Autodesk Fusion 360 part; units mm, degrees
(part 2 of 2)
component "05_magnet_11_N 弧形磁钢 内侧N极" placed x (1, 0, 0) y (0, 1, 0) z (0, 0, 1) at (0, 0, 0) in component "A 旋转总成 | ROTOR"
component "05_magnet_12_S 弧形磁钢 内侧S极" placed x (1, 0, 0) y (0, 1, 0) z (0, 0, 1) at (0, 0, 0) in component "A 旋转总成 | ROTOR"
component "05_magnet_13_N 弧形磁钢 内侧N极" placed x (1, 0, 0) y (0, 1, 0) z (0, 0, 1) at (0, 0, 0) in component "A 旋转总成 | ROTOR"
component "05_magnet_14_S 弧形磁钢 内侧S极" placed x (1, 0, 0) y (0, 1, 0) z (0, 0, 1) at (0, 0, 0) in component "A 旋转总成 | ROTOR"
component "10_inner_spacer 内圈隔垫" placed x (1, 0, 0) y (0, 1, 0) z (0, 0, 1) at (0, 0, 0) in component "A 旋转总成 | ROTOR"
component "13_sensor_magnet 两极径向测角磁铁" placed x (1, 0, 0) y (0, 1, 0) z (0, 0, 1) at (0, 0, 0) in component "A 旋转总成 | ROTOR"
component "06_stator_carrier 铝固定座" placed x (1, 0, 0) y (0, 1, 0) z (0, 0, 1) at (0, 0, 0) in component "B 固定总成 | STATOR + SENSOR"
component "07_stator_stack 12 槽叠片铁芯 H4" placed x (1, 0, 0) y (0, 1, 0) z (0, 0, 1) at (0, 0, 0) in component "B 固定总成 | STATOR + SENSOR"
component "08_coil_01_Ap Ap 32匝绕组包络" placed x (1, 0, 0) y (0, 1, 0) z (0, 0, 1) at (0, 0, 0) in component "B 固定总成 | STATOR + SENSOR"
component "08_coil_02_An An 32匝绕组包络" placed x (1, 0, 0) y (0, 1, 0) z (0, 0, 1) at (0, 0, 0) in component "B 固定总成 | STATOR + SENSOR"
component "08_coil_03_Bn Bn 32匝绕组包络" placed x (1, 0, 0) y (0, 1, 0) z (0, 0, 1) at (0, 0, 0) in component "B 固定总成 | STATOR + SENSOR"
component "08_coil_04_Bp Bp 32匝绕组包络" placed x (1, 0, 0) y (0, 1, 0) z (0, 0, 1) at (0, 0, 0) in component "B 固定总成 | STATOR + SENSOR"
component "08_coil_05_Cp Cp 32匝绕组包络" placed x (1, 0, 0) y (0, 1, 0) z (0, 0, 1) at (0, 0, 0) in component "B 固定总成 | STATOR + SENSOR"
component "08_coil_06_Cn Cn 32匝绕组包络" placed x (1, 0, 0) y (0, 1, 0) z (0, 0, 1) at (0, 0, 0) in component "B 固定总成 | STATOR + SENSOR"
component "08_coil_07_An An 32匝绕组包络" placed x (1, 0, 0) y (0, 1, 0) z (0, 0, 1) at (0, 0, 0) in component "B 固定总成 | STATOR + SENSOR"
component "08_coil_08_Ap Ap 32匝绕组包络" placed x (1, 0, 0) y (0, 1, 0) z (0, 0, 1) at (0, 0, 0) in component "B 固定总成 | STATOR + SENSOR"
component "08_coil_09_Bp Bp 32匝绕组包络" placed x (1, 0, 0) y (0, 1, 0) z (0, 0, 1) at (0, 0, 0) in component "B 固定总成 | STATOR + SENSOR"
component "08_coil_10_Bn Bn 32匝绕组包络" placed x (1, 0, 0) y (0, 1, 0) z (0, 0, 1) at (0, 0, 0) in component "B 固定总成 | STATOR + SENSOR"
component "08_coil_11_Cn Cn 32匝绕组包络" placed x (1, 0, 0) y (0, 1, 0) z (0, 0, 1) at (0, 0, 0) in component "B 固定总成 | STATOR + SENSOR"
component "08_coil_12_Cp Cp 32匝绕组包络" placed x (1, 0, 0) y (0, 1, 0) z (0, 0, 1) at (0, 0, 0) in component "B 固定总成 | STATOR + SENSOR"
component "09_bearing_1 MR52ZZ 轴承包络" placed x (1, 0, 0) y (0, 1, 0) z (0, 0, 1) at (0, 0, 0) in component "B 固定总成 | STATOR + SENSOR"
component "09_bearing_2 MR52ZZ 轴承包络" placed x (1, 0, 0) y (0, 1, 0) z (0, 0, 1) at (0, 0, 0) in component "B 固定总成 | STATOR + SENSOR"
component "11_lower_outer_retainer 轴承外圈挡环" placed x (1, 0, 0) y (0, 1, 0) z (0, 0, 1) at (0, 0, 0) in component "B 固定总成 | STATOR + SENSOR"
component "12_upper_outer_retainer 轴承外圈挡环" placed x (1, 0, 0) y (0, 1, 0) z (0, 0, 1) at (0, 0, 0) in component "B 固定总成 | STATOR + SENSOR"
component "14_sensor_flex 测角刚柔板包络" placed x (1, 0, 0) y (0, 1, 0) z (0, 0, 1) at (0, 0, 0) in component "B 固定总成 | STATOR + SENSOR"
component "15_MT6701_max_envelope 角度芯片最大包络" placed x (1, 0, 0) y (0, 1, 0) z (0, 0, 1) at (0, 0, 0) in component "B 固定总成 | STATOR + SENSOR"
component "16_sensor_decoupling 0201 去耦包络" placed x (1, 0, 0) y (0, 1, 0) z (0, 0, 1) at (0, 0, 0) in component "B 固定总成 | STATOR + SENSOR"
component "(Unsaved)" placed x (1, 0, 0) y (0, 1, 0) z (0, 0, 1) at (0, 0, 0) in component "05_magnet_01_N 弧形磁钢 内侧N极"
component "A 旋转总成 | ROTOR" placed x (1, 0, 0) y (0, 1, 0) z (0, 0, 1) at (0, 0, 0) in component "08_coil_10_Bn Bn 32匝绕组包络"
equation "grip_od_mm = 17 mm" comment "R0 geometry source; see build script for dependent sketch geometry"
equation "grip_id_mm = 16.4 mm" comment "R0 geometry source; see build script for dependent sketch geometry"
equation "rotor_bottom_z_mm = 1.2 mm" comment "R0 geometry source; see build script for dependent sketch geometry"
equation "top_z_mm = 8.8 mm" comment "R0 geometry source; see build script for dependent sketch geometry"
equation "rotor_yoke_id_mm = 15.4 mm" comment "R0 geometry source; see build script for dependent sketch geometry"
equation "rotor_yoke_top_z_mm = 8 mm" comment "R0 geometry source; see build script for dependent sketch geometry"
equation "cap_spigot_od_mm = 15.36 mm" comment "R0 geometry source; see build script for dependent sketch geometry"
equation "cap_spigot_id_mm = 14 mm" comment "R0 geometry source; see build script for dependent sketch geometry"
equation "cap_spigot_bottom_z_mm = 7.4 mm" comment "R0 geometry source; see build script for dependent sketch geometry"
equation "magnet_od_mm = 15.3 mm" comment "R0 geometry source; see build script for dependent sketch geometry"
equation "magnet_id_mm = 13.5 mm" comment "R0 geometry source; see build script for dependent sketch geometry"
equation "magnet_bottom_z_mm = 2.05 mm" comment "R0 geometry source; see build script for dependent sketch geometry"
equation "magnet_height_mm = 4.5 mm" comment "R0 geometry source; see build script for dependent sketch geometry"
equation "stator_od_mm = 13 mm" comment "R0 geometry source; see build script for dependent sketch geometry"
equation "stator_id_mm = 6.1 mm" comment "R0 geometry source; see build script for dependent sketch geometry"
equation "stator_yoke_od_mm = 8 mm" comment "R0 geometry source; see build script for dependent sketch geometry"
equation "stator_bottom_z_mm = 2.3 mm" comment "R0 geometry source; see build script for dependent sketch geometry"
equation "stator_stack_mm = 4 mm" comment "R0 geometry source; see build script for dependent sketch geometry"
equation "lamination_mm = 0.2 mm" comment "R0 geometry source; see build script for dependent sketch geometry"
equation "tooth_width_mm = 0.8 mm" comment "R0 geometry source; see build script for dependent sketch geometry"
equation "tooth_tip_root_radius_mm = 6.1 mm" comment "R0 geometry source; see build script for dependent sketch geometry"
equation "coil_r_min_mm = 4.2 mm" comment "R0 geometry source; see build script for dependent sketch geometry"
equation "coil_r_max_mm = 5.95 mm" comment "R0 geometry source; see build script for dependent sketch geometry"
equation "coil_half_width_mm = 0.98 mm" comment "R0 geometry source; see build script for dependent sketch geometry"
equation "coil_inner_half_width_mm = 0.5 mm" comment "R0 geometry source; see build script for dependent sketch geometry"
equation "coil_bottom_z_mm = 1.72 mm" comment "R0 geometry source; see build script for dependent sketch geometry"
equation "coil_top_z_mm = 6.88 mm" comment "R0 geometry source; see build script for dependent sketch geometry"
equation "carrier_base_od_mm = 14 mm" comment "R0 geometry source; see build script for dependent sketch geometry"
equation "carrier_base_thickness_mm = 0.6 mm" comment "R0 geometry source; see build script for dependent sketch geometry"
equation "carrier_post_od_mm = 6 mm" comment "R0 geometry source; see build script for dependent sketch geometry"
equation "bearing_od_mm = 5 mm" comment "R0 geometry source; see build script for dependent sketch geometry"
equation "bearing_id_mm = 2 mm" comment "R0 geometry source; see build script for dependent sketch geometry"
equation "bearing_width_mm = 2.5 mm" comment "R0 geometry source; see build script for dependent sketch geometry"
equation "bearing_lower_z_mm = 2.7 mm" comment "R0 geometry source; see build script for dependent sketch geometry"
equation "bearing_upper_z_mm = 5.3 mm" comment "R0 geometry source; see build script for dependent sketch geometry"
equation "bearing_outer_stop_id_mm = 4.5 mm" comment "R0 geometry source; see build script for dependent sketch geometry"
equation "bearing_inner_abutment_od_mm = 2.6 mm" comment "R0 geometry source; see build script for dependent sketch geometry"
equation "mount_pcd_mm = 10.8 mm" comment "R0 geometry source; see build script for dependent sketch geometry"
equation "mount_boss_od_mm = 2.4 mm" comment "R0 geometry source; see build script for dependent sketch geometry"
equation "mount_boss_top_z_mm = 1.5 mm" comment "R0 geometry source; see build script for dependent sketch geometry"
equation "mount_pilot_diameter_mm = 1.1 mm" comment "R0 geometry source; see build script for dependent sketch geometry"
equation "sensor_pcb_od_mm = 5.5 mm" comment "R0 geometry source; see build script for dependent sketch geometry"
equation "sensor_pcb_thickness_mm = 0.4 mm" comment "R0 geometry source; see build script for dependent sketch geometry"
equation "sensor_pocket_od_mm = 5.6 mm" comment "R0 geometry source; see build script for dependent sketch geometry"
equation "sensor_solder_z_mm = 0.05 mm" comment "R0 geometry source; see build script for dependent sketch geometry"
equation "sensor_magnet_od_mm = 4 mm" comment "R0 geometry source; see build script for dependent sketch geometry"
equation "sensor_magnet_height_mm = 0.5 mm" comment "R0 geometry source; see build script for dependent sketch geometry"
equation "sensor_magnet_bottom_z_mm = 1.88 mm" comment "R0 geometry source; see build script for dependent sketch geometry"
equation "case_base_y_mm = 2.5 mm" comment "R0 geometry source; see build script for dependent sketch geometry"
equation "d50 = 2 * ( grip_od_mm / 2 )"
equation "d51 = 2 * ( grip_id_mm / 2 )"
equation "d52 = rotor_bottom_z_mm"
equation "d53 = top_z_mm - rotor_bottom_z_mm"
equation "d58 = 2 * ( grip_id_mm / 2 )"
equation "d59 = 2 * ( rotor_yoke_id_mm / 2 )"
equation "d60 = rotor_bottom_z_mm"
equation "d61 = rotor_yoke_top_z_mm - rotor_bottom_z_mm"
equation "d63 = 2 * ( grip_id_mm / 2 )"
equation "d64 = 2 * ( bearing_id_mm / 2 )"
equation "d65 = rotor_yoke_top_z_mm"
equation "d66 = top_z_mm - rotor_yoke_top_z_mm"
equation "d68 = 2 * ( cap_spigot_od_mm / 2 )"
equation "d69 = 2 * ( cap_spigot_id_mm / 2 )"
equation "d70 = cap_spigot_bottom_z_mm"
equation "d71 = rotor_yoke_top_z_mm - cap_spigot_bottom_z_mm"
equation "d73 = 2 * ( bearing_inner_abutment_od_mm / 2 )"
equation "d74 = 2 * ( bearing_id_mm / 2 )"
equation "d75 = bearing_upper_z_mm + bearing_width_mm"
equation "d76 = rotor_yoke_top_z_mm - bearing_upper_z_mm - bearing_width_mm"
equation "d81 = 2 * ( bearing_id_mm / 2 )"
equation "d82 = bearing_lower_z_mm"
equation "d83 = top_z_mm - 0.15 mm - bearing_lower_z_mm"
equation "d85 = 2 * ( bearing_inner_abutment_od_mm / 2 )"
equation "d86 = bearing_lower_z_mm - 0.3 mm"
equation "d89 = magnet_bottom_z_mm"
equation "d90 = magnet_height_mm"
equation "d92 = magnet_bottom_z_mm"
equation "d93 = magnet_height_mm"
equation "d95 = magnet_bottom_z_mm"
equation "d96 = magnet_height_mm"
equation "d98 = magnet_bottom_z_mm"
equation "d99 = magnet_height_mm"
equation "d101 = magnet_bottom_z_mm"
equation "d102 = magnet_height_mm"
equation "d104 = magnet_bottom_z_mm"
equation "d105 = magnet_height_mm"
equation "d107 = magnet_bottom_z_mm"
equation "d108 = magnet_height_mm"
equation "d110 = magnet_bottom_z_mm"
equation "d111 = magnet_height_mm"
equation "d113 = magnet_bottom_z_mm"
equation "d114 = magnet_height_mm"
equation "d116 = magnet_bottom_z_mm"
equation "d117 = magnet_height_mm"
equation "d119 = magnet_bottom_z_mm"
equation "d120 = magnet_height_mm"
equation "d122 = magnet_bottom_z_mm"
equation "d123 = magnet_height_mm"
equation "d125 = magnet_bottom_z_mm"
equation "d126 = magnet_height_mm"
equation "d128 = magnet_bottom_z_mm"
equation "d129 = magnet_height_mm"
equation "d131 = 2 * ( carrier_base_od_mm / 2 )"
equation "d133 = carrier_base_thickness_mm"
equation "d135 = 2 * ( sensor_pocket_od_mm / 2 )"
equation "d137 = sensor_pcb_thickness_mm + 0.01 mm"
equation "d139 = 2 * ( bearing_od_mm / 2 )"
equation "d140 = sensor_pcb_thickness_mm"
equation "d141 = carrier_base_thickness_mm - sensor_pcb_thickness_mm + 0.01 mm"
equation "d143 = 2 * ( carrier_post_od_mm / 2 )"
equation "d144 = 2 * ( bearing_od_mm / 2 )"
equation "d145 = carrier_base_thickness_mm"
equation "d146 = bearing_upper_z_mm + bearing_width_mm - carrier_base_thickness_mm"
equation "d148 = 2 * ( bearing_od_mm / 2 )"
equation "d149 = 2 * ( bearing_outer_stop_id_mm / 2 )"
equation "d150 = bearing_lower_z_mm + bearing_width_mm"
equation "d151 = bearing_upper_z_mm - bearing_lower_z_mm - bearing_width_mm"
equation "d153 = 2 * ( mount_boss_od_mm / 2 )"
equation "d154 = carrier_base_thickness_mm"
equation "d155 = mount_boss_top_z_mm - carrier_base_thickness_mm"
equation "d157 = 2 * ( mount_pilot_diameter_mm / 2 )"
equation "d159 = mount_boss_top_z_mm - 0.24 mm"
equation "d161 = 2 * ( mount_boss_od_mm / 2 )"
equation "d162 = carrier_base_thickness_mm"
equation "d163 = mount_boss_top_z_mm - carrier_base_thickness_mm"
equation "d165 = 2 * ( mount_pilot_diameter_mm / 2 )"
equation "d167 = mount_boss_top_z_mm - 0.24 mm"
equation "d169 = 2 * ( mount_boss_od_mm / 2 )"
equation "d170 = carrier_base_thickness_mm"
equation "d171 = mount_boss_top_z_mm - carrier_base_thickness_mm"
equation "d173 = 2 * ( mount_pilot_diameter_mm / 2 )"
equation "d175 = mount_boss_top_z_mm - 0.24 mm"
equation "d183 = 2 * ( stator_yoke_od_mm / 2 )"
equation "d184 = 2 * ( stator_id_mm / 2 )"
equation "d185 = stator_bottom_z_mm"
equation "d186 = stator_stack_mm"
equation "d188 = stator_bottom_z_mm"
equation "d189 = stator_stack_mm"
equation "d191 = stator_bottom_z_mm"
equation "d192 = stator_stack_mm"
equation "d194 = stator_bottom_z_mm"
equation "d195 = stator_stack_mm"
equation "d197 = stator_bottom_z_mm"
equation "d198 = stator_stack_mm"
equation "d200 = stator_bottom_z_mm"
equation "d201 = stator_stack_mm"
equation "d203 = stator_bottom_z_mm"
equation "d204 = stator_stack_mm"
equation "d206 = stator_bottom_z_mm"
equation "d207 = stator_stack_mm"
equation "d209 = stator_bottom_z_mm"
equation "d210 = stator_stack_mm"
equation "d212 = stator_bottom_z_mm"
equation "d213 = stator_stack_mm"
equation "d215 = stator_bottom_z_mm"
equation "d216 = stator_stack_mm"
equation "d218 = stator_bottom_z_mm"
equation "d219 = stator_stack_mm"
equation "d221 = stator_bottom_z_mm"
equation "d222 = stator_stack_mm"
equation "d224 = stator_bottom_z_mm"
equation "d225 = stator_stack_mm"
equation "d227 = stator_bottom_z_mm"
equation "d228 = stator_stack_mm"
equation "d230 = stator_bottom_z_mm"
equation "d231 = stator_stack_mm"
equation "d233 = stator_bottom_z_mm"
equation "d234 = stator_stack_mm"
equation "d236 = stator_bottom_z_mm"
equation "d237 = stator_stack_mm"
equation "d239 = stator_bottom_z_mm"
equation "d240 = stator_stack_mm"
equation "d242 = stator_bottom_z_mm"
equation "d243 = stator_stack_mm"
equation "d245 = stator_bottom_z_mm"
equation "d246 = stator_stack_mm"
equation "d248 = stator_bottom_z_mm"
equation "d249 = stator_stack_mm"
equation "d251 = stator_bottom_z_mm"
equation "d252 = stator_stack_mm"
equation "d254 = stator_bottom_z_mm"
equation "d255 = stator_stack_mm"
equation "d257 = stator_bottom_z_mm"
equation "d258 = stator_stack_mm"
equation "d260 = coil_bottom_z_mm"
equation "d261 = coil_top_z_mm - coil_bottom_z_mm"
equation "d263 = stator_bottom_z_mm - 0.1 mm"
equation "d264 = stator_stack_mm + 0.2 mm"
equation "d266 = coil_bottom_z_mm"
equation "d267 = coil_top_z_mm - coil_bottom_z_mm"
equation "d269 = stator_bottom_z_mm - 0.1 mm"
equation "d270 = stator_stack_mm + 0.2 mm"
equation "d272 = coil_bottom_z_mm"
equation "d273 = coil_top_z_mm - coil_bottom_z_mm"
equation "d275 = stator_bottom_z_mm - 0.1 mm"
equation "d276 = stator_stack_mm + 0.2 mm"
equation "d278 = coil_bottom_z_mm"
equation "d279 = coil_top_z_mm - coil_bottom_z_mm"
equation "d281 = stator_bottom_z_mm - 0.1 mm"
equation "d282 = stator_stack_mm + 0.2 mm"
equation "d284 = coil_bottom_z_mm"
equation "d285 = coil_top_z_mm - coil_bottom_z_mm"
equation "d287 = stator_bottom_z_mm - 0.1 mm"
equation "d288 = stator_stack_mm + 0.2 mm"
equation "d290 = coil_bottom_z_mm"
equation "d291 = coil_top_z_mm - coil_bottom_z_mm"
equation "d293 = stator_bottom_z_mm - 0.1 mm"
equation "d294 = stator_stack_mm + 0.2 mm"
equation "d296 = coil_bottom_z_mm"
equation "d297 = coil_top_z_mm - coil_bottom_z_mm"
equation "d299 = stator_bottom_z_mm - 0.1 mm"
equation "d300 = stator_stack_mm + 0.2 mm"
equation "d302 = coil_bottom_z_mm"
equation "d303 = coil_top_z_mm - coil_bottom_z_mm"
equation "d305 = stator_bottom_z_mm - 0.1 mm"
equation "d306 = stator_stack_mm + 0.2 mm"
equation "d308 = coil_bottom_z_mm"
equation "d309 = coil_top_z_mm - coil_bottom_z_mm"
equation "d311 = stator_bottom_z_mm - 0.1 mm"
equation "d312 = stator_stack_mm + 0.2 mm"
equation "d314 = coil_bottom_z_mm"
equation "d315 = coil_top_z_mm - coil_bottom_z_mm"
equation "d317 = stator_bottom_z_mm - 0.1 mm"
equation "d318 = stator_stack_mm + 0.2 mm"
equation "d320 = coil_bottom_z_mm"
equation "d321 = coil_top_z_mm - coil_bottom_z_mm"
equation "d323 = stator_bottom_z_mm - 0.1 mm"
equation "d324 = stator_stack_mm + 0.2 mm"
equation "d326 = coil_bottom_z_mm"
equation "d327 = coil_top_z_mm - coil_bottom_z_mm"
equation "d329 = stator_bottom_z_mm - 0.1 mm"
equation "d330 = stator_stack_mm + 0.2 mm"
equation "d332 = 2 * ( bearing_od_mm / 2 )"
equation "d333 = 2 * ( bearing_id_mm / 2 )"
equation "d334 = bearing_lower_z_mm"
equation "d335 = bearing_width_mm"
equation "d337 = 2 * ( bearing_od_mm / 2 )"
equation "d338 = 2 * ( bearing_id_mm / 2 )"
equation "d339 = bearing_upper_z_mm"
equation "d340 = bearing_width_mm"
equation "d342 = 2 * ( bearing_inner_abutment_od_mm / 2 )"
equation "d343 = 2 * ( bearing_id_mm / 2 )"
equation "d344 = bearing_lower_z_mm + bearing_width_mm"
equation "d345 = bearing_upper_z_mm - bearing_lower_z_mm - bearing_width_mm"
equation "d347 = 2 * ( bearing_od_mm / 2 )"
equation "d348 = 2 * ( bearing_outer_stop_id_mm / 2 )"
equation "d349 = bearing_lower_z_mm - 0.2 mm"
equation "d352 = 2 * ( bearing_od_mm / 2 )"
equation "d353 = 2 * ( bearing_outer_stop_id_mm / 2 )"
equation "d354 = bearing_upper_z_mm + bearing_width_mm"
equation "d357 = 2 * ( sensor_magnet_od_mm / 2 )"
equation "d358 = sensor_magnet_bottom_z_mm"
equation "d359 = sensor_magnet_height_mm"
equation "d361 = 2 * ( sensor_pcb_od_mm / 2 )"
equation "d363 = sensor_pcb_thickness_mm"
named bodies: "01_grip_ring", "02_rotor_back_iron", "03_rotor_cap", "04_rotor_shaft", "05_magnet_01_N", "05_magnet_02_S", "05_magnet_03_N", "05_magnet_04_S", "05_magnet_05_N", "05_magnet_06_S", "05_magnet_07_N", "05_magnet_08_S", "05_magnet_09_N", "05_magnet_10_S", "05_magnet_11_N", "05_magnet_12_S", "05_magnet_13_N", "05_magnet_14_S", "06_stator_carrier", "07_stator_stack", "08_coil_01_Ap", "08_coil_02_An", "08_coil_03_Bn", "08_coil_04_Bp", "08_coil_05_Cp", "08_coil_06_Cn", "08_coil_07_An", "08_coil_08_Ap", "08_coil_09_Bp", "08_coil_10_Bn", "08_coil_11_Cn", "08_coil_12_Cp", "09_bearing_1", "09_bearing_2", "10_inner_spacer", "11_lower_outer_retainer", "12_upper_outer_retainer", "13_sensor_magnet", "14_sensor_flex", "15_MT6701_max_envelope", "16_sensor_decoupling"
